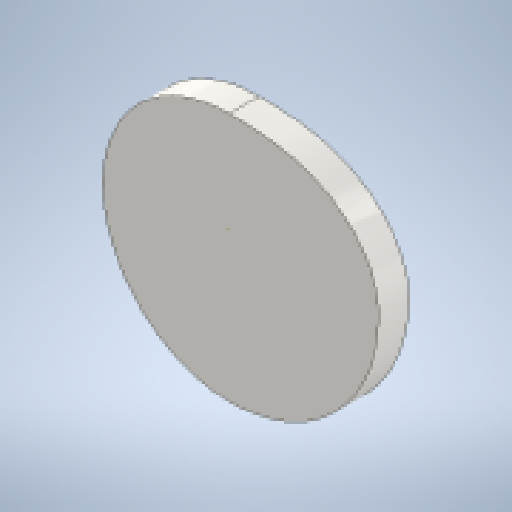
# Autodesk Inventor part: Disc Cam
Saved by Autodesk Inventor 2025.2 (Build 292293000, 293)
## iProperties
Created: 2025-05-16
Part Number: Disc Cam
Material: Stainless Steel, Austenitic
Document SubType Name: Modeling
Designer: laura
Manufacturer: Standard
Standards Organization: Custom
Density: 1 g/cm^3
Appearance: Steel
CustomPartVersion: 1
Author: laura
Autodesk Inventor part; units mm, degrees
ref_plane "YZ Plane" through (0, 0, 0) normal (1, 0, 0) x (0, 1, 0)
ref_plane "XZ Plane" through (0, 0, 0) normal (0, 1, 0) x (-1, 0, 0)
ref_plane "XY Plane" through (0, 0, 0) normal (0, 0, 1) x (1, 0, 0)
sketch "Main Sketch" plane through (0, 0, 0) normal (0, 0, 1) x (1, 0, 0)
  spline S0 degree 5 poles (0, 20) (0.6651, 20.0054) (1.8309, 19.9952) (3.7317, 19.947) (5.8663, 19.8431) (8.7293, 19.5568) (11.2965, 19.1367) (13.946, 18.4979) (16.4872, 17.6385) (18.9311, 16.5375) (21.2366, 15.1821) (23.3705, 13.5741) (25.2874, 11.7142) (26.9387, 9.6478) (28.2914, 7.3499) (29.2929, 4.9686) (29.9305, 2.2804) (30.0914, -0.0234) (29.8885, -3.3978) (29.4149, -6.256) (28.603, -9.3329) (27.4824, -12.2255) (26.0517, -15.0455) (24.3373, -17.6801) (22.3554, -20.1298) (20.1292, -22.3552) (17.6816, -24.3373) (15.0421, -26.0519) (12.2335, -27.4818) (9.3042, -28.6082) (6.257, -29.4225) (3.2057, -29.9099) (0.0131, -30.0857) (-2.9097, -29.9189) (-5.8951, -29.3837) (-8.7349, -28.5128) (-11.4617, -27.3177) (-14.01, -25.8241) (-16.3605, -24.0561) (-18.4774, -22.0457) (-20.3378, -19.8265) (-21.9208, -17.4352) (-23.2127, -14.9092) (-24.2046, -12.2866) (-24.8929, -9.6049) (-25.2792, -6.9005) (-25.3691, -4.2082) (-25.1725, -1.5603) (-24.7026, 1.0138) (-23.9755, 3.4874) (-23.0093, 5.8374) (-21.8237, 8.0439) (-20.4395, 10.0904) (-18.8774, 11.9636) (-17.1592, 13.6531) (-15.3033, 15.1515) (-13.3339, 16.4532) (-11.2588, 17.556) (-9.1191, 18.4558) (-6.9655, 19.1299) (-4.7589, 19.6315) (-2.8153, 19.8885) (-1.531, 19.9719) (-0.593, 19.9952) (0, 20) knots 0 0 0 0 0 0 0.020543 0.034068 0.050881 0.067505 0.084001 0.100421 0.116801 0.133165 0.149517 0.165848 0.182132 0.198333 0.214405 0.230763 0.247423 0.264409 0.281757 0.299515 0.317273 0.335031 0.352789 0.370547 0.388305 0.406063 0.423822 0.44158 0.459338 0.477096 0.494752 0.51231 0.529769 0.547126 0.564374 0.581606 0.598805 0.615959 0.633053 0.650076 0.667019 0.683871 0.700624 0.717272 0.733809 0.750232 0.766537 0.782724 0.798792 0.814744 0.830584 0.846316 0.861947 0.877486 0.892944 0.908332 0.923663 0.938954 0.954219 0.969478 0.981682 1 1 1 1 1 1
  point P0 (5.8623, 19.8092)
  point P1 (8.6394, 19.5261)
  point P2 (11.3321, 19.0777)
  point P3 (13.9457, 18.4353)
  point P4 (16.4746, 17.5735)
  point P5 (18.9011, 16.4717)
  point P6 (21.1964, 15.1171)
  point P7 (23.3217, 13.5067)
  point P8 (25.2319, 11.6499)
  point P9 (26.8787, 9.5701)
  point P10 (28.2148, 7.3055)
  point P11 (29.1987, 4.9093)
  point P12 (29.7992, 2.4482)
  point P13 (30, 0)
  point P14 (29.8357, -3.1359)
  point P15 (29.3444, -6.2374)
  point P16 (28.5317, -9.2705)
  point P17 (27.4064, -12.2021)
  point P18 (25.9808, -15)
  point P19 (24.2705, -17.6336)
  point P20 (22.2943, -20.0739)
  point P21 (20.0739, -22.2943)
  point P22 (17.6336, -24.2705)
  point P23 (15, -25.9808)
  point P24 (12.2021, -27.4064)
  point P25 (9.2705, -28.5317)
  point P26 (6.2374, -29.3444)
  point P27 (3.1359, -29.8357)
  point P28 (0, -30)
  point P29 (-2.9576, -29.8229)
  point P30 (-5.8789, -29.2953)
  point P31 (-8.7173, -28.4277)
  point P32 (-11.4294, -27.237)
  point P33 (-13.9752, -25.7456)
  point P34 (-16.3195, -23.9808)
  point P35 (-18.4319, -21.9737)
  point P36 (-20.287, -19.7586)
  point P37 (-21.8654, -17.3718)
  point P38 (-23.1528, -14.851)
  point P39 (-24.1406, -12.2341)
  point P40 (-24.8255, -9.5587)
  point P41 (-25.2088, -6.8612)
  point P42 (-25.2966, -4.1761)
  point P43 (-25.0987, -1.5358)
  point P44 (-24.6284, 1.0304)
  point P45 (-23.9019, 3.496)
  point P46 (-22.9373, 5.8379)
  point P47 (-21.7544, 8.0365)
  point P48 (-20.3738, 10.0754)
  point P49 (-18.8165, 11.9414)
  point P50 (-17.1036, 13.6243)
  point P51 (-15.2553, 15.1166)
  point P52 (-13.291, 16.4134)
  point P53 (-11.2292, 17.5114)
  point P54 (-9.0866, 18.4092)
  point P55 (-6.879, 19.1064)
  point P56 (-4.6203, 19.6034)
  point P57 (-2.3234, 19.901)
  constraints: 60 other
extrude "Cam" add sketch "Main Sketch" along normal blind 6
sketch "Sketch2" plane through (0, 0, 6) normal (0, 0, 1) x (1, 0, 0)
  circle A0 centre (0, 0) radius 4
  dimension "d4" = 8
  constraints: 1 centre point, 1 coincident
  measures "d4" diameter of A0
extrude "Extrusion2" cut sketch "Sketch2" against normal through all
equation "\"d4\" = d_eje"
equation "\"d_eje\" = 8"
body "Solid1"
